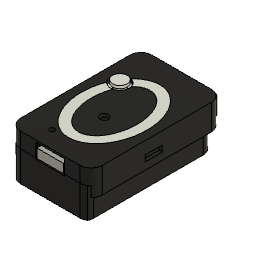
character_case (Autodesk Fusion 360 design; units mm, degrees)
description: Orbit O case. Card sealed inside, shells still open. 5 mm chain bail on the back. Orbit inlaid flush, button hat is the planet on the ring. See cad/character/PRINT.txt.
part number: 2026-10-25-17-23-30-498
part number: 2026-10-25-17-23-31-388
part number: 2026-10-25-17-23-31-567
part number: 2026-10-25-17-23-32-594
part number: 2026-10-25-17-23-34-708
Autodesk Fusion 360 part; units mm, degrees
ref_plane "WorkPlane1" through (0, 0, 9.1) normal (0, 0, 1) x (1, 0, 0) in component "Electronics"
sketch "PCB" plane through (0, 0, 9.1) normal (0, 0, 1) x (1, 0, 0) in component "Electronics"
  line L0 (0, 0) -> (23, 0)
  line L1 (23, 0) -> (23, 38)
  line L2 (23, 38) -> (0, 38)
  line L3 (0, 38) -> (0, 0)
extrude "Extrude1" add sketch "PCB" along normal blind 1.6 makes body 1 in component "Electronics"
ref_plane "WorkPlane2" through (0, 0, 10.7) normal (0, 0, 1) x (1, 0, 0) in component "Electronics"
sketch "XIAO" plane through (0, 0, 10.7) normal (0, 0, 1) x (1, 0, 0) in component "Electronics"
  line L0 (2.6, 0) -> (20.4, 0)
  line L1 (20.4, 0) -> (20.4, 21)
  line L2 (20.4, 21) -> (2.6, 21)
  line L3 (2.6, 21) -> (2.6, 0)
extrude "Extrude2" add sketch "XIAO" along normal blind 3.5 separate body makes body 2 in component "Electronics"
ref_plane "WorkPlane3" through (0, 0, 10.7) normal (0, 0, 1) x (1, 0, 0) in component "Electronics"
sketch "USB_C" plane through (0, 0, 10.7) normal (0, 0, 1) x (1, 0, 0) in component "Electronics"
  line L0 (6.8, -2.2) -> (16.2, -2.2)
  line L1 (16.2, -2.2) -> (16.2, 0.4)
  line L2 (16.2, 0.4) -> (6.8, 0.4)
  line L3 (6.8, 0.4) -> (6.8, -2.2)
extrude "Extrude3" add sketch "USB_C" along normal blind 3.2 separate body makes body 3 in component "Electronics"
ref_plane "WorkPlane4" through (0, 0, 10.7) normal (0, 0, 1) x (1, 0, 0) in component "Electronics"
sketch "SD_socket" plane through (0, 0, 10.7) normal (0, 0, 1) x (1, 0, 0) in component "Electronics"
  line L0 (8.3, 24.9) -> (22, 24.9)
  line L1 (22, 24.9) -> (22, 37.9)
  line L2 (22, 37.9) -> (8.3, 37.9)
  line L3 (8.3, 37.9) -> (8.3, 24.9)
extrude "Extrude4" add sketch "SD_socket" along normal blind 1.5 separate body makes body 4 in component "Electronics"
ref_plane "WorkPlane5" through (0, 0, 10.95) normal (0, 0, 1) x (1, 0, 0) in component "Electronics"
sketch "SD_mouth" plane through (0, 0, 10.95) normal (0, 0, 1) x (1, 0, 0) in component "Electronics"
  line L0 (9.8, 37.6) -> (20.8, 37.6)
  line L1 (20.8, 37.6) -> (20.8, 41.2)
  line L2 (20.8, 41.2) -> (9.8, 41.2)
  line L3 (9.8, 41.2) -> (9.8, 37.6)
extrude "Extrude5" add sketch "SD_mouth" along normal blind 1 separate body makes body 5 in component "Electronics"
ref_plane "WorkPlane6" through (0, 0, 10.7) normal (0, 0, 1) x (1, 0, 0) in component "Electronics"
sketch "Button" plane through (0, 0, 10.7) normal (0, 0, 1) x (1, 0, 0) in component "Electronics"
  line L0 (1.7, 28.7) -> (5.9, 28.7)
  line L1 (5.9, 28.7) -> (5.9, 31.7)
  line L2 (5.9, 31.7) -> (1.7, 31.7)
  line L3 (1.7, 31.7) -> (1.7, 28.7)
extrude "Extrude6" add sketch "Button" along normal blind 1.8 separate body makes body 6 in component "Electronics"
ref_plane "WorkPlane7" through (0, 0, 10.7) normal (0, 0, 1) x (1, 0, 0) in component "Electronics"
sketch "Cap_22uF" plane through (0, 0, 10.7) normal (0, 0, 1) x (1, 0, 0) in component "Electronics"
  line L0 (13, 22.275) -> (15, 22.275)
  line L1 (15, 22.275) -> (15, 23.525)
  line L2 (15, 23.525) -> (13, 23.525)
  line L3 (13, 23.525) -> (13, 22.275)
extrude "Extrude7" add sketch "Cap_22uF" along normal blind 1.15 separate body makes body 7 in component "Electronics"
ref_plane "WorkPlane8" through (0, 0, 1.2) normal (0, 0, 1) x (1, 0, 0) in component "Electronics"
sketch "Cell" plane through (0, 0, 1.2) normal (0, 0, 1) x (1, 0, 0) in component "Electronics"
  line L0 (1.5, 8) -> (21.5, 8)
  line L1 (21.5, 8) -> (21.5, 38)
  line L2 (21.5, 38) -> (1.5, 38)
  line L3 (1.5, 38) -> (1.5, 8)
extrude "Extrude8" add sketch "Cell" along normal blind 6 separate body makes body 8 in component "Electronics"
sketch "Back_outline" plane through (0, 0, 0) normal (0, 0, 1) x (1, 0, 0) in component "Back shell"
  line L0 (2.45, -3.8) -> (20.55, -3.8)
  arc A0 (20.55, -3.8) -> (24.55, 0.2) centre (20.55, 0.2) ccw
  line L1 (24.55, 0.2) -> (24.55, 39)
  arc A1 (24.55, 39) -> (20.55, 43) centre (20.55, 39) ccw
  line L2 (20.55, 43) -> (2.45, 43)
  arc A2 (2.45, 43) -> (-1.55, 39) centre (2.45, 39) ccw
  line L3 (-1.55, 39) -> (-1.55, 0.2)
  arc A3 (-1.55, 0.2) -> (2.45, -3.8) centre (2.45, 0.2) ccw
extrude "Extrude1'" add sketch "Back_outline" along normal blind 10.7 separate body makes body 9 in component "Back shell"
ref_plane "WorkPlane1" through (0, 0, 9.1) normal (0, 0, 1) x (1, 0, 0) in component "Back shell"
sketch "Board_pocket" plane through (0, 0, 9.1) normal (0, 0, 1) x (1, 0, 0) in component "Back shell"
  line L0 (-0.35, -2.6) -> (23.35, -2.6)
  line L1 (23.35, -2.6) -> (23.35, 41.8)
  line L2 (23.35, 41.8) -> (-0.35, 41.8)
  line L3 (-0.35, 41.8) -> (-0.35, -2.6)
extrude "Extrude2'" cut sketch "Board_pocket" along normal blind 1.8 bodies 9 in component "Back shell"
ref_plane "WorkPlane2" through (0, 0, 1.2) normal (0, 0, 1) x (1, 0, 0) in component "Back shell"
sketch "Cell_pocket" plane through (0, 0, 1.2) normal (0, 0, 1) x (1, 0, 0) in component "Back shell"
  line L0 (1.2, 7.7) -> (21.8, 7.7)
  line L1 (21.8, 7.7) -> (21.8, 38.3)
  line L2 (21.8, 38.3) -> (1.2, 38.3)
  line L3 (1.2, 38.3) -> (1.2, 7.7)
extrude "Extrude3'" cut sketch "Cell_pocket" along normal blind 7.9 bodies 9 in component "Back shell"
ref_plane "WorkPlane3" through (0, 0, 1.2) normal (0, 0, 1) x (1, 0, 0) in component "Back shell"
sketch "Wire_bay" plane through (0, 0, 1.2) normal (0, 0, 1) x (1, 0, 0) in component "Back shell"
  line L0 (0.8, 0.6) -> (22.2, 0.6)
  line L1 (22.2, 0.6) -> (22.2, 8.4)
  line L2 (22.2, 8.4) -> (0.8, 8.4)
  line L3 (0.8, 8.4) -> (0.8, 0.6)
extrude "Extrude4'" cut sketch "Wire_bay" along normal blind 7.9 bodies 9 in component "Back shell"
ref_plane "WorkPlane4" through (0, 0, 9.1) normal (0, 0, 1) x (1, 0, 0) in component "Back shell"
sketch "Lock_S_left" plane through (0, 0, 9.1) normal (0, 0, 1) x (1, 0, 0) in component "Back shell"
  line L0 (0.6, -1.4) -> (4.4, -1.4)
  line L1 (4.4, -1.4) -> (4.4, -0.15)
  line L2 (4.4, -0.15) -> (0.6, -0.15)
  line L3 (0.6, -0.15) -> (0.6, -1.4)
extrude "Extrude5'" add sketch "Lock_S_left" along normal blind 1.6 bodies 9 in component "Back shell"
ref_plane "WorkPlane5" through (0, 0, 9.1) normal (0, 0, 1) x (1, 0, 0) in component "Back shell"
sketch "Lock_S_right" plane through (0, 0, 9.1) normal (0, 0, 1) x (1, 0, 0) in component "Back shell"
  line L0 (18.6, -1.4) -> (22.4, -1.4)
  line L1 (22.4, -1.4) -> (22.4, -0.15)
  line L2 (22.4, -0.15) -> (18.6, -0.15)
  line L3 (18.6, -0.15) -> (18.6, -1.4)
extrude "Extrude6'" add sketch "Lock_S_right" along normal blind 1.6 bodies 9 in component "Back shell"
ref_plane "WorkPlane6" through (0, 0, 9.1) normal (0, 0, 1) x (1, 0, 0) in component "Back shell"
sketch "Lock_N_left" plane through (0, 0, 9.1) normal (0, 0, 1) x (1, 0, 0) in component "Back shell"
  line L0 (0.4, 38.15) -> (2.6, 38.15)
  line L1 (2.6, 38.15) -> (2.6, 39.3)
  line L2 (2.6, 39.3) -> (0.4, 39.3)
  line L3 (0.4, 39.3) -> (0.4, 38.15)
extrude "Extrude7'" add sketch "Lock_N_left" along normal blind 1.6 bodies 9 in component "Back shell"
ref_plane "WorkPlane7" through (0, 0, 9.1) normal (0, 0, 1) x (1, 0, 0) in component "Back shell"
sketch "Lock_N_right" plane through (0, 0, 9.1) normal (0, 0, 1) x (1, 0, 0) in component "Back shell"
  line L0 (21, 38.15) -> (22.6, 38.15)
  line L1 (22.6, 38.15) -> (22.6, 39.3)
  line L2 (22.6, 39.3) -> (21, 39.3)
  line L3 (21, 39.3) -> (21, 38.15)
extrude "Extrude8'" add sketch "Lock_N_right" along normal blind 1.6 bodies 9 in component "Back shell"
ref_plane "WorkPlane8" through (0, 0, 9.1) normal (0, 0, 1) x (1, 0, 0) in component "Back shell"
sketch "Lock_W" plane through (0, 0, 9.1) normal (0, 0, 1) x (1, 0, 0) in component "Back shell"
  line L0 (-1.5, 14) -> (-0.5, 14)
  line L1 (-0.5, 14) -> (-0.5, 18)
  line L2 (-0.5, 18) -> (-1.5, 18)
  line L3 (-1.5, 18) -> (-1.5, 14)
extrude "Extrude9" add sketch "Lock_W" along normal blind 1.6 bodies 9 in component "Back shell"
ref_plane "WorkPlane9" through (0, 0, 9.1) normal (0, 0, 1) x (1, 0, 0) in component "Back shell"
sketch "Lock_E" plane through (0, 0, 9.1) normal (0, 0, 1) x (1, 0, 0) in component "Back shell"
  line L0 (23.5, 14) -> (24.5, 14)
  line L1 (24.5, 14) -> (24.5, 18)
  line L2 (24.5, 18) -> (23.5, 18)
  line L3 (23.5, 18) -> (23.5, 14)
extrude "Extrude10" add sketch "Lock_E" along normal blind 1.6 bodies 9 in component "Back shell"
ref_plane "WorkPlane10" through (0, 0, 9.1) normal (0, 0, 1) x (1, 0, 0) in component "Back shell"
sketch "Side_gap_W" plane through (0, 0, 9.1) normal (0, 0, 1) x (1, 0, 0) in component "Back shell"
  line L0 (-0.5, -0.2) -> (-0.35, -0.2)
  line L1 (-0.35, -0.2) -> (-0.35, 38.2)
  line L2 (-0.35, 38.2) -> (-0.5, 38.2)
  line L3 (-0.5, 38.2) -> (-0.5, -0.2)
extrude "Extrude11" cut sketch "Side_gap_W" along normal blind 1.8 bodies 9 in component "Back shell"
ref_plane "WorkPlane11" through (0, 0, 9.1) normal (0, 0, 1) x (1, 0, 0) in component "Back shell"
sketch "Side_gap_E" plane through (0, 0, 9.1) normal (0, 0, 1) x (1, 0, 0) in component "Back shell"
  line L0 (23.35, -0.2) -> (23.5, -0.2)
  line L1 (23.5, -0.2) -> (23.5, 38.2)
  line L2 (23.5, 38.2) -> (23.35, 38.2)
  line L3 (23.35, 38.2) -> (23.35, -0.2)
extrude "Extrude12" cut sketch "Side_gap_E" along normal blind 1.8 bodies 9 in component "Back shell"
ref_plane "WorkPlane12" through (0, 0, 10.5) normal (0, 0, 1) x (1, 0, 0) in component "Back shell"
sketch "Clip_W" plane through (0, 0, 10.5) normal (0, 0, 1) x (1, 0, 0) in component "Back shell"
  line L0 (-1.4, 20) -> (-0.5, 20)
  line L1 (-0.5, 20) -> (-0.5, 22.8)
  line L2 (-0.5, 22.8) -> (-1.4, 22.8)
  line L3 (-1.4, 22.8) -> (-1.4, 20)
extrude "Extrude13" add sketch "Clip_W" along normal blind 0.7 bodies 9 in component "Back shell"
ref_plane "WorkPlane13" through (0, 0, 10.5) normal (0, 0, 1) x (1, 0, 0) in component "Back shell"
sketch "Clip_E" plane through (0, 0, 10.5) normal (0, 0, 1) x (1, 0, 0) in component "Back shell"
  line L0 (23.5, 20) -> (24.4, 20)
  line L1 (24.4, 20) -> (24.4, 22.8)
  line L2 (24.4, 22.8) -> (23.5, 22.8)
  line L3 (23.5, 22.8) -> (23.5, 20)
extrude "Extrude14" add sketch "Clip_E" along normal blind 0.7 bodies 9 in component "Back shell"
ref_plane "WorkPlane14" through (7.5, 0, 0) normal (1, 0, 0) x (0, 1, 0) in component "Back shell"
sketch "Chain_neck" plane through (7.5, 0, 0) normal (1, 0, 0) x (0, 0, -1) in component "Back shell"
  line L0 (-5.5, 42.6) -> (-1.2, 42.6)
  arc A0 (-1.2, 42.6) -> (0, 43.8) centre (-1.2, 43.8) ccw
  line L1 (0, 43.8) -> (0, 44.15)
  arc A1 (0, 44.15) -> (-1.2, 45.35) centre (-1.2, 44.15) ccw
  line L2 (-1.2, 45.35) -> (-5.5, 45.35)
  arc A2 (-5.5, 45.35) -> (-6.7, 44.15) centre (-5.5, 44.15) ccw
  line L3 (-6.7, 44.15) -> (-6.7, 43.8)
  arc A3 (-6.7, 43.8) -> (-5.5, 42.6) centre (-5.5, 43.8) ccw
extrude "Extrude15" add sketch "Chain_neck" along normal blind 8 bodies 9 in component "Back shell"
ref_plane "WorkPlane15" through (7.5, 0, 0) normal (1, 0, 0) x (0, 1, 0) in component "Back shell"
sketch "Chain_bail" plane through (7.5, 0, 0) normal (1, 0, 0) x (0, 0, -1) in component "Back shell"
  line L0 (-6.6, 44.75) -> (-1.6, 44.75)
  arc A0 (-1.6, 44.75) -> (0, 46.35) centre (-1.6, 46.35) ccw
  line L1 (0, 46.35) -> (0, 51.35)
  arc A1 (0, 51.35) -> (-1.6, 52.95) centre (-1.6, 51.35) ccw
  line L2 (-1.6, 52.95) -> (-6.6, 52.95)
  arc A2 (-6.6, 52.95) -> (-8.2, 51.35) centre (-6.6, 51.35) ccw
  line L3 (-8.2, 51.35) -> (-8.2, 46.35)
  arc A3 (-8.2, 46.35) -> (-6.6, 44.75) centre (-6.6, 46.35) ccw
extrude "Extrude16" add sketch "Chain_bail" along normal blind 8 bodies 9 in component "Back shell"
ref_plane "WorkPlane16" through (7.3, 0, 0) normal (1, 0, 0) x (0, 1, 0) in component "Back shell"
sketch "Chain_hole" plane through (7.3, 0, 0) normal (1, 0, 0) x (0, 0, -1) in component "Back shell"
  circle A0 centre (-4.1, 48.85) radius 2.5
extrude "Extrude17" cut sketch "Chain_hole" along normal blind 8.4 bodies 9 in component "Back shell"
ref_plane "WorkPlane17" through (0, 0, 7.75) normal (0, 0, 1) x (1, 0, 0) in component "Back shell"
sketch "Snap_pocket_L_0" plane through (0, 0, 7.75) normal (0, 0, 1) x (1, 0, 0) in component "Back shell"
  line L0 (-1.85, 7.15) -> (-1, 7.15)
  line L1 (-1, 7.15) -> (-1, 15.85)
  line L2 (-1, 15.85) -> (-1.85, 15.85)
  line L3 (-1.85, 15.85) -> (-1.85, 7.15)
extrude "Extrude18" cut sketch "Snap_pocket_L_0" along normal blind 2.45 bodies 9 in component "Back shell"
ref_plane "WorkPlane18" through (0, 0, 7.75) normal (0, 0, 1) x (1, 0, 0) in component "Back shell"
sketch "Snap_pocket_L_1" plane through (0, 0, 7.75) normal (0, 0, 1) x (1, 0, 0) in component "Back shell"
  line L0 (-1.85, 24.15) -> (-1, 24.15)
  line L1 (-1, 24.15) -> (-1, 32.85)
  line L2 (-1, 32.85) -> (-1.85, 32.85)
  line L3 (-1.85, 32.85) -> (-1.85, 24.15)
extrude "Extrude19" cut sketch "Snap_pocket_L_1" along normal blind 2.45 bodies 9 in component "Back shell"
ref_plane "WorkPlane19" through (0, 0, 7.75) normal (0, 0, 1) x (1, 0, 0) in component "Back shell"
sketch "Snap_pocket_R_0" plane through (0, 0, 7.75) normal (0, 0, 1) x (1, 0, 0) in component "Back shell"
  line L0 (24, 7.15) -> (24.85, 7.15)
  line L1 (24.85, 7.15) -> (24.85, 15.85)
  line L2 (24.85, 15.85) -> (24, 15.85)
  line L3 (24, 15.85) -> (24, 7.15)
extrude "Extrude20" cut sketch "Snap_pocket_R_0" along normal blind 2.45 bodies 9 in component "Back shell"
ref_plane "WorkPlane20" through (0, 0, 7.75) normal (0, 0, 1) x (1, 0, 0) in component "Back shell"
sketch "Snap_pocket_R_1" plane through (0, 0, 7.75) normal (0, 0, 1) x (1, 0, 0) in component "Back shell"
  line L0 (24, 24.15) -> (24.85, 24.15)
  line L1 (24.85, 24.15) -> (24.85, 32.85)
  line L2 (24.85, 32.85) -> (24, 32.85)
  line L3 (24, 32.85) -> (24, 24.15)
extrude "Extrude21" cut sketch "Snap_pocket_R_1" along normal blind 2.45 bodies 9 in component "Back shell"
ref_plane "WorkPlane1" through (0, 0, 10.7) normal (0, 0, 1) x (1, 0, 0) in component "Front shell"
sketch "Front_outline" plane through (0, 0, 10.7) normal (0, 0, 1) x (1, 0, 0) in component "Front shell"
  line L0 (1, -5.25) -> (22, -5.25)
  arc A0 (22, -5.25) -> (26, -1.25) centre (22, -1.25) ccw
  line L1 (26, -1.25) -> (26, 40.45)
  arc A1 (26, 40.45) -> (22, 44.45) centre (22, 40.45) ccw
  line L2 (22, 44.45) -> (1, 44.45)
  arc A2 (1, 44.45) -> (-3, 40.45) centre (1, 40.45) ccw
  line L3 (-3, 40.45) -> (-3, -1.25)
  arc A3 (-3, -1.25) -> (1, -5.25) centre (1, -1.25) ccw
extrude "Extrude1''" add sketch "Front_outline" along normal blind 5.5 separate body makes body 10 in component "Front shell"
ref_plane "WorkPlane2" through (0, 0, 10.7) normal (0, 0, 1) x (1, 0, 0) in component "Front shell"
sketch "Front_skirt" plane through (0, 0, 10.7) normal (0, 0, 1) x (1, 0, 0) in component "Front shell"
  line L0 (1, -5.25) -> (22, -5.25)
  arc A0 (22, -5.25) -> (26, -1.25) centre (22, -1.25) ccw
  line L1 (26, -1.25) -> (26, 40.45)
  arc A1 (26, 40.45) -> (22, 44.45) centre (22, 40.45) ccw
  line L2 (22, 44.45) -> (1, 44.45)
  arc A2 (1, 44.45) -> (-3, 40.45) centre (1, 40.45) ccw
  line L3 (-3, 40.45) -> (-3, -1.25)
  arc A3 (-3, -1.25) -> (1, -5.25) centre (1, -1.25) ccw
  line L4 (0.75, -4.05) -> (22.25, -4.05)
  arc A4 (22.25, -4.05) -> (24.8, -1.5) centre (22.25, -1.5) ccw
  line L5 (24.8, -1.5) -> (24.8, 40.7)
  arc A5 (24.8, 40.7) -> (22.25, 43.25) centre (22.25, 40.7) ccw
  line L6 (22.25, 43.25) -> (0.75, 43.25)
  arc A6 (0.75, 43.25) -> (-1.8, 40.7) centre (0.75, 40.7) ccw
  line L7 (-1.8, 40.7) -> (-1.8, -1.5)
  arc A7 (-1.8, -1.5) -> (0.75, -4.05) centre (0.75, -1.5) ccw
extrude "Extrude2''" add sketch "Front_skirt" against normal blind 3.6 bodies 10 in component "Front shell"
ref_plane "WorkPlane3" through (0, 0, 10.7) normal (0, 0, 1) x (1, 0, 0) in component "Front shell"
sketch "Front_cavity" plane through (0, 0, 10.7) normal (0, 0, 1) x (1, 0, 0) in component "Front shell"
  line L0 (-0.35, -2.6) -> (23.35, -2.6)
  line L1 (23.35, -2.6) -> (23.35, 41.8)
  line L2 (23.35, 41.8) -> (-0.35, 41.8)
  line L3 (-0.35, 41.8) -> (-0.35, -2.6)
extrude "Extrude3''" cut sketch "Front_cavity" along normal blind 4.3 bodies 10 in component "Front shell"
ref_plane "WorkPlane4" through (0, 7.5, 0) normal (0, 1, 0) x (0, 0, 1) in component "Front shell"
sketch "Snap_catch_L_0" plane through (0, 7.5, 0) normal (0, 1, 0) x (1, 0, 0) in component "Front shell"
  line L0 (-2.1, -8) -> (-1.68, -8)
  line L1 (-1.68, -8) -> (-1.15, -9.1)
  line L2 (-1.15, -9.1) -> (-1.15, -9.9)
  line L3 (-1.15, -9.9) -> (-2.1, -9.9)
  line L4 (-2.1, -9.9) -> (-2.1, -8)
extrude "Extrude4''" add sketch "Snap_catch_L_0" along normal blind 8 bodies 10 in component "Front shell"
ref_plane "WorkPlane5" through (0, 24.5, 0) normal (0, 1, 0) x (0, 0, 1) in component "Front shell"
sketch "Snap_catch_L_1" plane through (0, 24.5, 0) normal (0, 1, 0) x (1, 0, 0) in component "Front shell"
  line L0 (-2.1, -8) -> (-1.68, -8)
  line L1 (-1.68, -8) -> (-1.15, -9.1)
  line L2 (-1.15, -9.1) -> (-1.15, -9.9)
  line L3 (-1.15, -9.9) -> (-2.1, -9.9)
  line L4 (-2.1, -9.9) -> (-2.1, -8)
extrude "Extrude5''" add sketch "Snap_catch_L_1" along normal blind 8 bodies 10 in component "Front shell"
ref_plane "WorkPlane6" through (0, 7.5, 0) normal (0, 1, 0) x (0, 0, 1) in component "Front shell"
sketch "Snap_catch_R_0" plane through (0, 7.5, 0) normal (0, 1, 0) x (1, 0, 0) in component "Front shell"
  line L0 (25.1, -8) -> (24.68, -8)
  line L1 (24.68, -8) -> (24.15, -9.1)
  line L2 (24.15, -9.1) -> (24.15, -9.9)
  line L3 (24.15, -9.9) -> (25.1, -9.9)
  line L4 (25.1, -9.9) -> (25.1, -8)
extrude "Extrude6''" add sketch "Snap_catch_R_0" along normal blind 8 bodies 10 in component "Front shell"
ref_plane "WorkPlane7" through (0, 24.5, 0) normal (0, 1, 0) x (0, 0, 1) in component "Front shell"
sketch "Snap_catch_R_1" plane through (0, 24.5, 0) normal (0, 1, 0) x (1, 0, 0) in component "Front shell"
  line L0 (25.1, -8) -> (24.68, -8)
  line L1 (24.68, -8) -> (24.15, -9.1)
  line L2 (24.15, -9.1) -> (24.15, -9.9)
  line L3 (24.15, -9.9) -> (25.1, -9.9)
  line L4 (25.1, -9.9) -> (25.1, -8)
extrude "Extrude7''" add sketch "Snap_catch_R_1" along normal blind 8 bodies 10 in component "Front shell"
ref_plane "WorkPlane8" through (0, 0, -0.4) normal (0, 0, 1) x (1, 0, 0) in component "Front shell"
sketch "USB_trim" plane through (0, 0, -0.4) normal (0, 0, 1) x (1, 0, 0) in component "Front shell"
  line L0 (-4, -6.25) -> (27, -6.25)
  line L1 (27, -6.25) -> (27, -2.2)
  line L2 (27, -2.2) -> (-4, -2.2)
  line L3 (-4, -2.2) -> (-4, -6.25)
extrude "Extrude22" cut sketch "USB_trim" along normal blind 17.2 bodies 9 in component "Back shell"
extrude "Extrude8''" cut sketch "USB_trim" along normal blind 17.2 bodies 10 in component "Front shell"
ref_plane "WorkPlane9" through (0, 0, 10.7) normal (0, 0, 1) x (1, 0, 0) in component "Front shell"
sketch "USB_wall" plane through (0, 0, 10.7) normal (0, 0, 1) x (1, 0, 0) in component "Front shell"
  line L0 (-0.35, -2.2) -> (23.35, -2.2)
  line L1 (23.35, -2.2) -> (23.35, -1)
  line L2 (23.35, -1) -> (-0.35, -1)
  line L3 (-0.35, -1) -> (-0.35, -2.2)
extrude "Extrude9'" add sketch "USB_wall" along normal blind 4.3 bodies 10 in component "Front shell"
ref_plane "WorkPlane21" through (0, 0, 9.1) normal (0, 0, 1) x (1, 0, 0) in component "Back shell"
sketch "USB_wall_back" plane through (0, 0, 9.1) normal (0, 0, 1) x (1, 0, 0) in component "Back shell"
  line L0 (-0.35, -2.2) -> (23.35, -2.2)
  line L1 (23.35, -2.2) -> (23.35, -1)
  line L2 (23.35, -1) -> (-0.35, -1)
  line L3 (-0.35, -1) -> (-0.35, -2.2)
extrude "Extrude23" add sketch "USB_wall_back" along normal blind 1.6 bodies 9 in component "Back shell"
ref_plane "WorkPlane10" through (0, 0, 10.2) normal (0, 0, 1) x (1, 0, 0) in component "Front shell"
sketch "USB_port" plane through (0, 0, 10.2) normal (0, 0, 1) x (1, 0, 0) in component "Front shell"
  line L0 (7.3, -2.7) -> (15.7, -2.7)
  arc A0 (15.7, -2.7) -> (16.7, -1.7) centre (15.7, -1.7) ccw
  line L1 (16.7, -1.7) -> (16.7, -1.6)
  arc A1 (16.7, -1.6) -> (15.7, -0.6) centre (15.7, -1.6) ccw
  line L2 (15.7, -0.6) -> (7.3, -0.6)
  arc A2 (7.3, -0.6) -> (6.3, -1.6) centre (7.3, -1.6) ccw
  line L3 (6.3, -1.6) -> (6.3, -1.7)
  arc A3 (6.3, -1.7) -> (7.3, -2.7) centre (7.3, -1.7) ccw
extrude "Extrude24" cut sketch "USB_port" along normal blind 5.3 bodies 9 in component "Back shell"
extrude "Extrude10'" cut sketch "USB_port" along normal blind 5.3 bodies 10 in component "Front shell"
ref_plane "WorkPlane11" through (0, 0, -0.4) normal (0, 0, 1) x (1, 0, 0) in component "Front shell"
sketch "USB_round_L" plane through (0, 0, -0.4) normal (0, 0, 1) x (1, 0, 0) in component "Front shell"
  line L0 (-3.6, -2.8) -> (0.95, -2.8)
  line L1 (0.95, -2.8) -> (0.95, 1.75)
  line L2 (0.95, 1.75) -> (-3.6, 1.75)
  line L3 (-3.6, 1.75) -> (-3.6, -2.8)
  circle A0 centre (1, 1.8) radius 4
extrude "Extrude25" cut sketch "USB_round_L" along normal blind 17.2 contours L0 L1 L2 L3 A0 bodies 9 in component "Back shell"
extrude "Extrude11'" cut sketch "USB_round_L" along normal blind 17.2 contours L0 L1 L2 L3 A0 bodies 10 in component "Front shell"
ref_plane "WorkPlane12" through (0, 0, -0.4) normal (0, 0, 1) x (1, 0, 0) in component "Front shell"
sketch "USB_round_R" plane through (0, 0, -0.4) normal (0, 0, 1) x (1, 0, 0) in component "Front shell"
  line L0 (22.05, -2.8) -> (26.6, -2.8)
  line L1 (26.6, -2.8) -> (26.6, 1.75)
  line L2 (26.6, 1.75) -> (22.05, 1.75)
  line L3 (22.05, 1.75) -> (22.05, -2.8)
  circle A0 centre (22, 1.8) radius 4
extrude "Extrude26" cut sketch "USB_round_R" along normal blind 17.2 contours L0 L1 L2 L3 A0 bodies 9 in component "Back shell"
extrude "Extrude12'" cut sketch "USB_round_R" along normal blind 17.2 contours L0 L1 L2 L3 A0 bodies 10 in component "Front shell"
ref_plane "WorkPlane13" through (0, 0, 15) normal (0, 0, 1) x (1, 0, 0) in component "Front shell"
sketch "Mic_hole" plane through (0, 0, 15) normal (0, 0, 1) x (1, 0, 0) in component "Front shell"
  circle A0 centre (11.5, 17) radius 1.5
extrude "Extrude13'" cut sketch "Mic_hole" along normal blind 1.6 bodies 10 in component "Front shell"
ref_plane "WorkPlane14" through (0, 0, 15) normal (0, 0, 1) x (1, 0, 0) in component "Front shell"
sketch "LED_hole" plane through (0, 0, 15) normal (0, 0, 1) x (1, 0, 0) in component "Front shell"
  circle A0 centre (6.2, 3.8) radius 0.9
extrude "Extrude14'" cut sketch "LED_hole" along normal blind 1.6 bodies 10 in component "Front shell"
ref_plane "WorkPlane15" through (0, 0, 15) normal (0, 0, 1) x (1, 0, 0) in component "Front shell"
sketch "Button_hole" plane through (0, 0, 15) normal (0, 0, 1) x (1, 0, 0) in component "Front shell"
  circle A0 centre (3.8, 30.2) radius 3.3
extrude "Extrude15'" cut sketch "Button_hole" along normal blind 1.6 bodies 10 in component "Front shell"
ref_plane "WorkPlane16" through (0, 0, 16.2) normal (0, 0, 1) x (1, 0, 0) in component "Front shell"
sketch "Orbit_Inlay" plane through (0, 0, 16.2) normal (0, 0, 1) x (1, 0, 0) in component "Front shell"
  ellipse E0 centre (11.5, 20.5) end of major axis (11.5, 36.7) minor radius 11.6
  line L0 (11.5, 4.3) -> (11.5, 36.7) construction
  line L1 (23.1, 20.5) -> (-0.1, 20.5) construction
  ellipse E1 centre (11.5, 20.5) end of major axis (11.5, 33.2) minor radius 8.1
  line L2 (11.5, 7.8) -> (11.5, 33.2) construction
  line L3 (19.6, 20.5) -> (3.4, 20.5) construction
  constraint coincident E0 L0.start
  constraint coincident E0 L0.end
  constraint coincident E0 L1.start
  constraint coincident E0 L1.end
  constraint coincident E1 L2.start
  constraint coincident E1 L2.end
  constraint coincident E1 L3.start
  constraint coincident E1 L3.end
extrude "Extrude16'" add sketch "Orbit_Inlay" against normal blind 0.6 separate body makes body 11 in component "Front shell"
extrude "Extrude17'" cut sketch "Orbit_Inlay" against normal blind 0.6 bodies 10 in component "Front shell"
ref_plane "WorkPlane17" through (0, 0, 16.2) normal (0, 0, 1) x (1, 0, 0) in component "Front shell"
sketch "Planet_seam" plane through (0, 0, 16.2) normal (0, 0, 1) x (1, 0, 0) in component "Front shell"
  circle A0 centre (3.8, 30.2) radius 3.3
extrude "Extrude18'" cut sketch "Planet_seam" against normal blind 2.2 bodies 10 11 in component "Front shell"
ref_plane "WorkPlane18" through (0, 0, 9.6) normal (0, 0, 1) x (1, 0, 0) in component "Front shell"
sketch "Nail_0" plane through (0, 0, 9.6) normal (0, 0, 1) x (1, 0, 0) in component "Front shell"
  line L0 (-3.2, 17) -> (-1.7, 17)
  line L1 (-1.7, 17) -> (-1.7, 23)
  line L2 (-1.7, 23) -> (-3.2, 23)
  line L3 (-3.2, 23) -> (-3.2, 17)
extrude "Extrude27" cut sketch "Nail_0" along normal blind 2.2 bodies 9 in component "Back shell"
extrude "Extrude19'" cut sketch "Nail_0" along normal blind 2.2 bodies 10 in component "Front shell"
ref_plane "WorkPlane19" through (0, 0, 9.6) normal (0, 0, 1) x (1, 0, 0) in component "Front shell"
sketch "Nail_1" plane through (0, 0, 9.6) normal (0, 0, 1) x (1, 0, 0) in component "Front shell"
  line L0 (24.7, 17) -> (26.2, 17)
  line L1 (26.2, 17) -> (26.2, 23)
  line L2 (26.2, 23) -> (24.7, 23)
  line L3 (24.7, 23) -> (24.7, 17)
extrude "Extrude28" cut sketch "Nail_1" along normal blind 2.2 bodies 9 in component "Back shell"
extrude "Extrude20'" cut sketch "Nail_1" along normal blind 2.2 bodies 10 in component "Front shell"
ref_plane "WorkPlane1" through (0, 0, 12.85) normal (0, 0, 1) x (1, 0, 0) in component "Button hat"
sketch "Hat_disc" plane through (0, 0, 12.85) normal (0, 0, 1) x (1, 0, 0) in component "Button hat"
  circle A0 centre (3.8, 30.2) radius 3.7
extrude "Extrude1'''" add sketch "Hat_disc" along normal blind 2.15 separate body makes body 12 in component "Button hat"
ref_plane "WorkPlane2" through (0, 0, 15) normal (0, 0, 1) x (1, 0, 0) in component "Button hat"
sketch "Hat_shaft" plane through (0, 0, 15) normal (0, 0, 1) x (1, 0, 0) in component "Button hat"
  circle A0 centre (3.8, 30.2) radius 1.9
extrude "Extrude2'''" add sketch "Hat_shaft" along normal blind 1.2 bodies 12 in component "Button hat"
ref_plane "WorkPlane3" through (0, 0, 16.2) normal (0, 0, 1) x (1, 0, 0) in component "Button hat"
sketch "Hat_head" plane through (0, 0, 16.2) normal (0, 0, 1) x (1, 0, 0) in component "Button hat"
  circle A0 centre (3.8, 30.2) radius 2.6
extrude "Extrude3'''" add sketch "Hat_head" along normal blind 1 bodies 12 in component "Button hat"
component "Electronics" placed x (1, 0, 0) y (0, 1, 0) z (0, 0, 1) at (0, 0, 0)
component "Back shell" placed x (1, 0, 0) y (0, 1, 0) z (0, 0, 1) at (0, 0, 0)
component "Front shell" placed x (1, 0, 0) y (0, 1, 0) z (0, 0, 1) at (0, 0, 0)
component "Button hat" placed x (1, 0, 0) y (0, 1, 0) z (0, 0, 1) at (0, 0, 0)
equation "d121 = -( 3.60 mm )"
equation "d189 = -( 0.60 mm )"
equation "d191 = -( 0.60 mm )"
equation "d195 = -( 2.20 mm )"
named bodies: "PCB", "XIAO", "USB_C", "SD_socket", "SD_mouth", "Button", "Cap_22uF", "Cell", "Back_Shell", "Front_Shell", "Orbit_Inlay", "Button_Hat"
